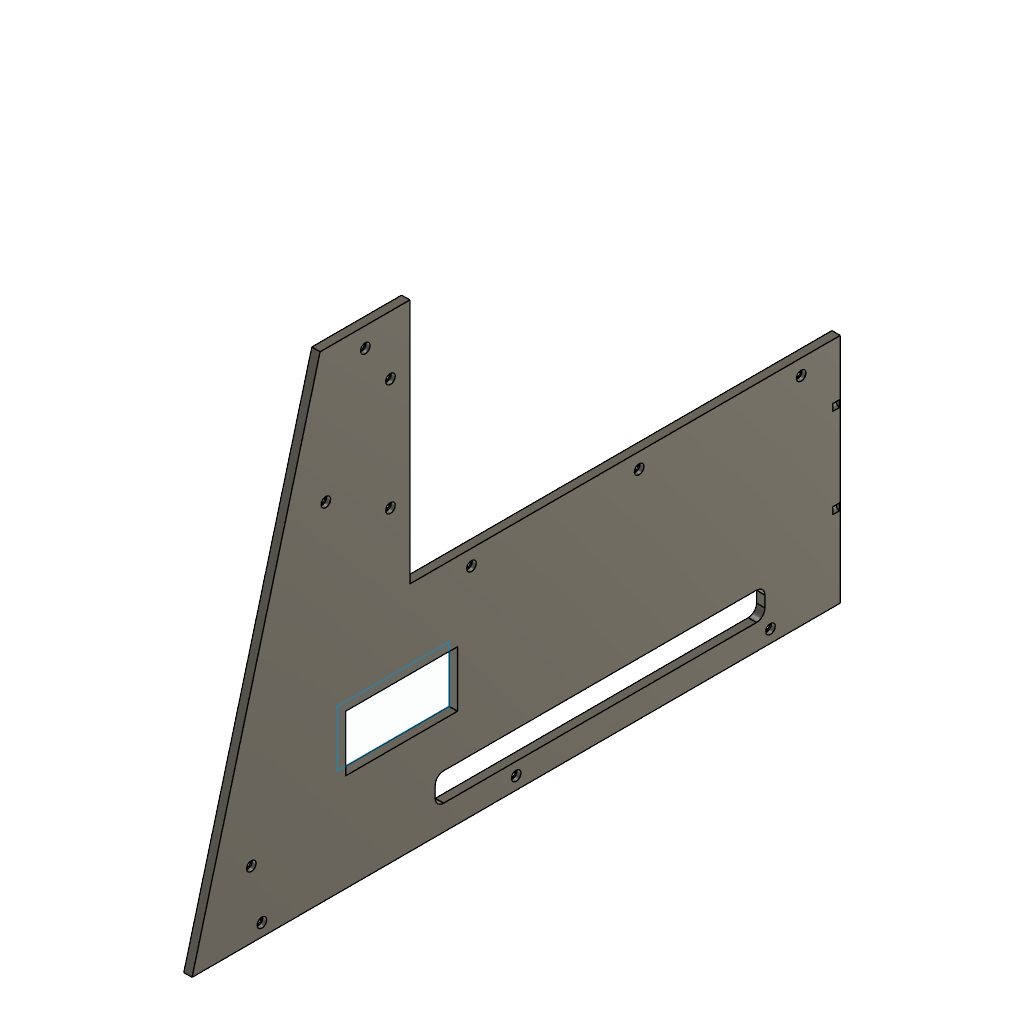
Side_L (Autodesk Fusion 360 design; units mm, degrees)
part number: 2026-10-19-10-28-37-204
Autodesk Fusion 360 part; units mm, degrees
sketch "Side_L_skin" plane through (0, 0, 0) normal (1, 0, 0) x (0, 0, -1)
  line L0 (0, 0) -> (-171, 45.8193)
  line L1 (-171, 45.8193) -> (-171, 78)
  line L2 (-171, 78) -> (-83, 78)
  line L3 (-83, 78) -> (-83, 232)
  line L4 (-83, 232) -> (0, 232)
  line L5 (0, 232) -> (0, 0)
extrude "Side_L_skin (1)" add sketch "Side_L_skin" against normal blind 3 from surface at -101
sketch "Side_L_screws_hole" plane through (0, 0, 0) normal (1, 0, 0) x (0, 0, -1)
  circle A0 centre (-4.5, 25) radius 1.7
  circle A1 centre (-4.5, 116) radius 1.7
  circle A2 centre (-4.5, 207) radius 1.7
  circle A3 centre (-23.908, 21.2106) radius 1.7
  circle A4 centre (-123.3984, 47.8689) radius 1.7
  circle A5 centre (-164, 62) radius 1.7
  circle A6 centre (-110, 71) radius 1.7
  circle A7 centre (-150, 71) radius 1.7
  circle A8 centre (-77.5, 100) radius 1.7
  circle A9 centre (-77.5, 160) radius 1.7
  circle A10 centre (-77.5, 218) radius 1.7
extrude "Side_L_screws_hole (1)" cut sketch "Side_L_screws_hole" along normal blind 4 from surface at -104.5
sketch "Side_L_screws_cone" plane through (0, 0, 0) normal (1, 0, 0) x (0, 0, -1)
  circle A0 centre (-4.5, 25) radius 3.8
  circle A1 centre (-4.5, 116) radius 3.8
  circle A2 centre (-4.5, 207) radius 3.8
  circle A3 centre (-23.908, 21.2106) radius 3.8
  circle A4 centre (-123.3984, 47.8689) radius 3.8
  circle A5 centre (-164, 62) radius 3.8
  circle A6 centre (-110, 71) radius 3.8
  circle A7 centre (-150, 71) radius 3.8
  circle A8 centre (-77.5, 100) radius 3.8
  circle A9 centre (-77.5, 160) radius 3.8
  circle A10 centre (-77.5, 218) radius 3.8
extrude "Side_L_screws_cone (1)" cut sketch "Side_L_screws_cone" along normal blind 2.1 draft -45 from surface at -104.5
sketch "Side_L_door_detent" plane through (0, 0, 0) normal (0, 1, 0) x (1, 0, 0)
  circle A0 centre (-101, -30) radius 1.2
  circle A1 centre (-101, -62) radius 1.2
extrude "Side_L_door_detent (1)" cut sketch "Side_L_door_detent" along normal blind 2.4 from surface at 229.3
sketch "printer_back_openings" plane through (0, 0, 0) normal (1, 0, 0) x (0, 0, -1)
  line L0 (-12, 87) -> (-16, 87)
  line L1 (-19, 90) -> (-19, 202)
  line L2 (-16, 205) -> (-12, 205)
  line L3 (-9, 202) -> (-9, 90)
  arc A0 (-19, 90) -> (-16, 87) centre (-16, 90) ccw
  arc A1 (-16, 205) -> (-19, 202) centre (-16, 202) ccw
  arc A2 (-9, 202) -> (-12, 205) centre (-12, 202) ccw
  arc A3 (-12, 87) -> (-9, 90) centre (-12, 90) ccw
  circle A4 centre (-44, 82) radius 7.5
  constraint tangent L0 A0
  constraint tangent L1 A0
  constraint tangent L1 A1
  constraint tangent L2 A1
  constraint tangent L2 A2
  constraint tangent L3 A2
  constraint tangent L3 A3
  constraint tangent L0 A3
extrude "printer_back_openings (1)" cut sketch "printer_back_openings" against normal blind 4 from surface at -100.5
sketch "sketch 887" plane through (-104, 0, 0) normal (-1, 0, 0) x (0, -1, 0)
  line L0 (-55, 35) -> (-95, 35)
  line L1 (-55, 55) -> (-55, 35)
  line L2 (-95, 55) -> (-55, 55)
  line L3 (-95, 35) -> (-95, 55)
extrude "Extrude7" cut sketch "sketch 887" against normal blind 5
equation "d614 = -( 3.00 mm )"
equation "d1135 = -( 4 mm )"
named bodies: "Side_L"
